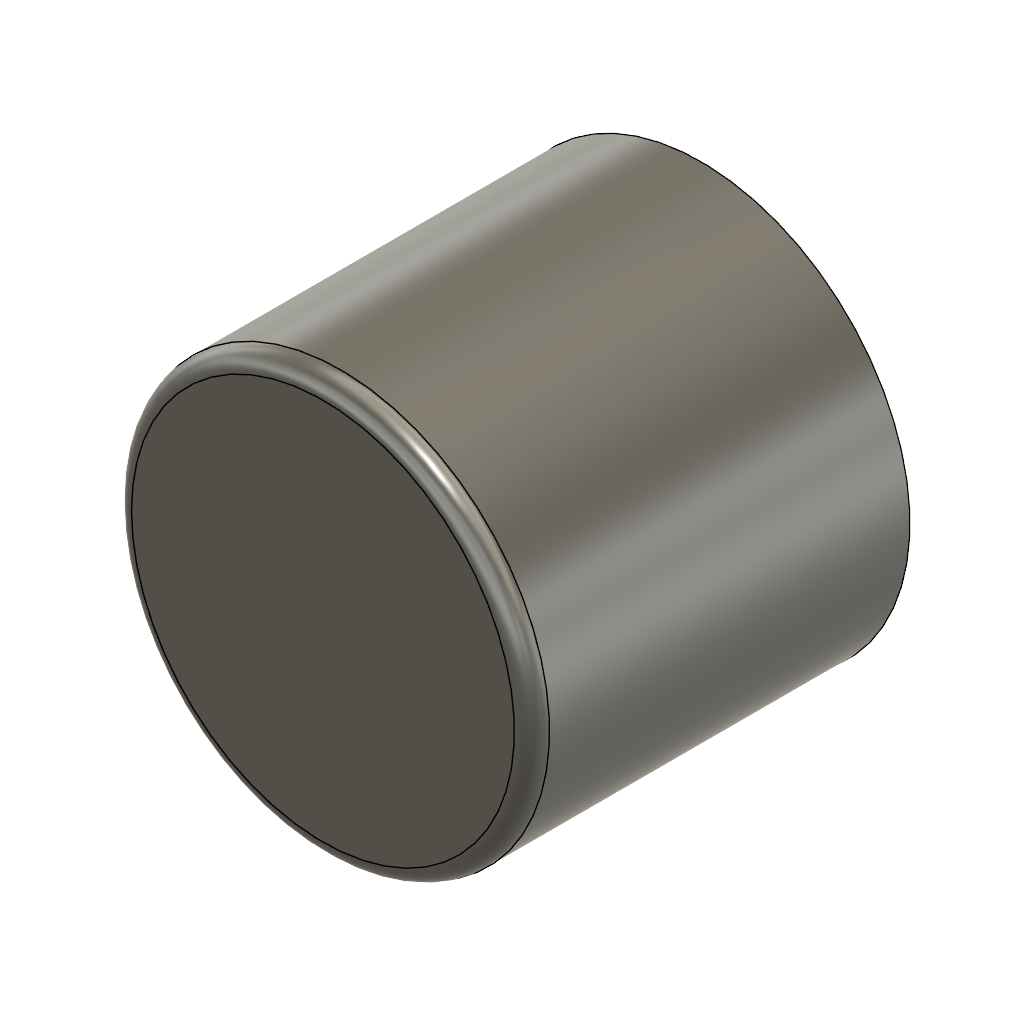
Native (Autodesk Fusion 360 design; units mm, degrees)
part number: 2026-11-25-22-41-42-270
Autodesk Fusion 360 part; units mm, degrees
sketch "Disc sketch" plane through (0, 0, 0) normal (0, 0, 1) x (1, 0, 0)
  circle A0 centre (0, 0) radius 13.1
extrude "Disc extrude" add sketch "Disc sketch" along normal blind 23.7
fillet "Rim round" radius 1.1 1 edges at (-12.2135, -4.7372, 23.7)
